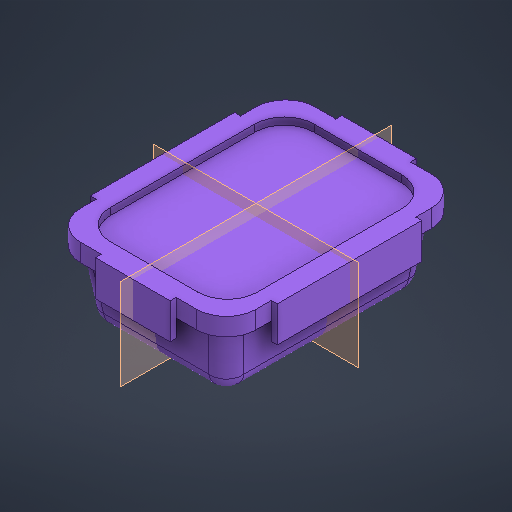
# Autodesk Inventor part: TUPPERWARE
Saved by Autodesk Inventor 2026.1 (Build 301233020, 233B)
## iProperties
Created: 2026-06-04
Part Number: TUPPERWARE
Material: Plastique ABS
Document SubType Name: Modeling
Designer: matpo
Density: 1.06 g/cm^3
Appearance: Violet
Author: matpo
Autodesk Inventor part; units mm, degrees
ref_plane "YZ Plane" through (0, 0, 0) normal (1, 0, 0) x (0, 1, 0)
ref_plane "XZ Plane" through (0, 0, 0) normal (0, 1, 0) x (-1, 0, 0)
sketch "Esquisse1" plane through (0, 0, 0) normal (0, 1, 0) x (-1, 0, 0)
  line L0 (-57.5, 82.5) -> (57.5, 82.5)
  line L1 (57.5, 82.5) -> (57.5, -82.5)
  line L2 (57.5, -82.5) -> (-57.5, -82.5)
  line L3 (-57.5, -82.5) -> (-57.5, 82.5)
  line L4 (-57.5, 82.5) -> (57.5, -82.5) construction
  line L5 (57.5, 82.5) -> (-57.5, -82.5) construction
  line L6 (-65, 90) -> (65, 90)
  line L7 (65, 90) -> (65, -90)
  line L8 (65, -90) -> (-65, -90)
  line L9 (-65, -90) -> (-65, 90)
  line L10 (-65, 90) -> (65, -90) construction
  line L11 (65, 90) -> (-65, -90) construction
  line L12 (-74, 99) -> (74, 99)
  line L13 (74, 99) -> (74, -99)
  line L14 (74, -99) -> (-74, -99)
  line L15 (-74, -99) -> (-74, 99)
  line L16 (-74, 99) -> (74, -99) construction
  line L17 (74, 99) -> (-74, -99) construction
  point P0 (0, 0)
  dimension "d0" = 115
  dimension "d1" = 165
  dimension "d2" = 130
  dimension "d3" = 180
  dimension "d9" = 148
  dimension "d10" = 198
  constraints: 36 end point, 6 midpoint, 6 parallel, 3 horizontal, 3 perpendicular
  measures "d0" distance of L1.end L2.end
  measures "d1" distance of L0.end L1.end
  measures "d2" distance of L7.end L8.end
  measures "d3" distance of L6.end L7.end
  measures "d9" distance of L13.end L14.end
  measures "d10" distance of L12.end L13.end
extrude "Extrusion1" add sketch "Esquisse1" along normal blind 60 contours L0 L1 L2 L3 | L6 L7 L8 L9 | L12 L13 L14 L15
ref_plane "Plan de construction1" through (0, 55, 0) normal (0, 1, 0) x (1, 0, 0)
sketch "Esquisse3" plane through (0, 55, 0) normal (0, 1, 0) x (1, 0, 0)
  line L0 (-65, -90) -> (-65, 90) projected
  line L1 (65, -90) -> (-65, -90) projected
  line L2 (-65, 90) -> (65, 90) projected
  line L3 (65, 90) -> (65, -90) projected
  line L4 (74, 99) -> (-74, 99) projected
  line L5 (74, -99) -> (74, 99) projected
  line L6 (-74, -99) -> (74, -99) projected
  line L7 (-74, 99) -> (-74, -99) projected
extrude "Extrusion2" cut sketch "Esquisse3" against normal through all
sketch "Esquisse4" plane through (-65, 55, 90) normal (0, 0, 1) x (1, 0, 0)
  line L0 (130, -55) -> (0, -55) projected
  line L1 (130, 0) -> (130, -55) projected
  line L2 (130, 0) -> (0, 0) projected
  line L3 (0, 0) -> (0, -55) projected
  line L4 (7.5, -55) -> (0, 0)
  line L5 (122.5, -55) -> (130, 0)
  point P0 (65, -55)
  constraints: 4 end point
extrude "Extrusion3" cut sketch "Esquisse4" against normal through all contours L0 L5 L1 | L0 L3 L4
sketch "Esquisse5" plane through (0, 0, 0) normal (1, 0, 0) x (0, 1, 0)
  line L0 (0, -90) -> (55, -90) projected
  line L1 (0, 90) -> (0, -90) projected
  line L2 (55, 90) -> (0, 90) projected
  line L3 (55, 90) -> (55, -90) projected
  line L4 (0, -82.5) -> (55, -90)
  line L5 (0, 82.5) -> (55, 90)
  point P0 (0, 0)
  constraints: 4 end point
extrude "Extrusion4" cut sketch "Esquisse5" along normal through all both and the other way through all contours L1 L4 L0 | L5 L1 L2
sketch "Esquisse6" plane through (0, 60, 0) normal (0, 1, 0) x (1, 0, 0)
  line L0 (74, 99) -> (-74, 99) projected
  line L1 (-74, 99) -> (-74, -99) projected
  line L2 (-74, -99) -> (74, -99) projected
  line L3 (74, -99) -> (74, 99) projected
  line L4 (69, 61) -> (79, 61)
  line L5 (79, 61) -> (79, -61)
  line L6 (79, -61) -> (69, -61)
  line L7 (69, -61) -> (69, 61)
  line L8 (69, 61) -> (79, -61) construction
  line L9 (79, 61) -> (69, -61) construction
  line L10 (0, 99) -> (0, -99) construction
  line L11 (-74, 0) -> (74, 0) construction
  line L12 (-31.5, -94) -> (31.5, -94)
  line L13 (31.5, -94) -> (31.5, -104)
  line L14 (31.5, -104) -> (-31.5, -104)
  line L15 (-31.5, -104) -> (-31.5, -94)
  line L16 (-31.5, -94) -> (31.5, -104) construction
  line L17 (31.5, -94) -> (-31.5, -104) construction
  line L18 (-69, 61) -> (-79, 61)
  line L19 (-79, 61) -> (-79, -61)
  line L20 (-79, -61) -> (-69, -61)
  line L21 (-69, -61) -> (-69, 61)
  line L22 (-31.5, 94) -> (31.5, 94)
  line L23 (31.5, 94) -> (31.5, 104)
  line L24 (31.5, 104) -> (-31.5, 104)
  line L25 (-31.5, 104) -> (-31.5, 94)
  point P0 (0, 0)
  point P1 (-74, -61)
  point P2 (-74, 61)
  point P3 (31.5, -99)
  point P4 (-31.5, -99)
  point P5 (74, 61)
  point P6 (74, -61)
  point P7 (-31.5, 99)
  point P8 (31.5, 99)
  dimension "d19" = 10
  dimension "d20" = 122
  dimension "d21" = 63
  dimension "d22" = 10
  constraints: 44 end point, 8 midpoint, 8 symmetric about line, 4 parallel, 3 perpendicular, 2 horizontal
  measures "d19" distance of L5.end L6.end
  measures "d20" distance of L4.end L5.end
  measures "d21" distance of L13.end L14.end
  measures "d22" distance of L12.end L13.end
extrude "Extrusion5" add sketch "Esquisse6" along normal blind 10
fillet "Congé1" radius 15 8 edges at (-61.25, 27.5, -86.25) (-57.5, 0, 0) (0, 0, -82.5) (61.25, 27.5, -86.25) (-61.25, 27.5, 86.25) (61.25, 27.5, 86.25) (0, 0, 82.5) (57.5, 0, 0)
fillet "Congé2" radius 25 4 edges at (74, 62.5, -99) (74, 62.5, 99) (-74, 62.5, 99) (-74, 62.5, -99)
sketch "Esquisse7" plane through (0, 60, 0) normal (0, -1, 0) x (1, 0, 0)
  line L0 (-74, -61) -> (-74, 61) projected
  line L1 (-79, 61) -> (-74, 61) projected
  line L2 (-79, -61) -> (-79, 61) projected
  line L3 (-74, -61) -> (-79, -61) projected
  line L4 (31.5, -99) -> (-31.5, -99) projected
  line L5 (-31.5, -104) -> (-31.5, -99) projected
  line L6 (31.5, -104) -> (-31.5, -104) projected
  line L7 (31.5, -99) -> (31.5, -104) projected
  line L8 (74, 61) -> (74, -61) projected
  line L9 (79, -61) -> (74, -61) projected
  line L10 (79, 61) -> (79, -61) projected
  line L11 (74, 61) -> (79, 61) projected
  line L12 (-31.5, 99) -> (31.5, 99) projected
  line L13 (31.5, 104) -> (31.5, 99) projected
  line L14 (-31.5, 104) -> (31.5, 104) projected
  line L15 (-31.5, 99) -> (-31.5, 104) projected
  point P0 (0, 0)
extrude "Extrusion6" add sketch "Esquisse7" along normal blind 20
sketch "Esquisse8" plane through (0, 70, 0) normal (0, 1, 0) x (1, 0, 0)
  line L0 (-37, 86) -> (37, 86)
  line L1 (62, 61) -> (62, -61)
  line L2 (37, -86) -> (-37, -86)
  line L3 (-62, -61) -> (-62, 61)
  line L4 (-62, 86) -> (62, -86) construction
  line L5 (62, 86) -> (-62, -86) construction
  arc A0 (37, -86) -> (62, -61) centre (37, -61) ccw
  arc A1 (-62, -61) -> (-37, -86) centre (-37, -61) ccw
  arc A2 (-37, 86) -> (-62, 61) centre (-37, 61) ccw
  arc A3 (62, 61) -> (37, 86) centre (37, 61) ccw
  point P0 (0, 0)
  dimension "d27" = 124
  dimension "d28" = 172
  dimension "d29" = 25
  constraints: 12 end point, 8 point on circle, 8 point on line, 8 tangent, 4 centre point, 3 equal radius, 2 midpoint, 2 parallel, 1 horizontal, 1 perpendicular
  measures "d27" distance of L4.end L5.end
  measures "d28" distance of L5.start L4.end
  measures "d29" radius of A0
extrude "Extrusion7" cut sketch "Esquisse8" against normal blind 6
ref_plane "Plan de construction3" through (0, 70, 61) normal (1, 0, 0) x (0, 0, -1)
sketch "Esquisse11" plane through (0, 70, 61) normal (1, 0, 0) x (0, 0, -1)
  arc A0 (-23.2691, -57.0267) -> (-8.4066, -70) centre (-8.4066, -55) ccw projected
  line L0 (-23.2691, -57.0267) -> (-29, -15) projected
  arc A1 (130.4066, -70) -> (145.2691, -57.0267) centre (130.4066, -55) ccw projected
  line L1 (151, -15) -> (145.2691, -57.0267) projected
  line L2 (160, -15) -> (135, -15) projected
  line L3 (-13, -15) -> (-38, -15) projected
  line L4 (130.4066, -70) -> (-8.4066, -70) projected
  line L5 (-28.1679, -10) -> (-21.7828, -56.824)
  arc A2 (-21.7828, -56.824) -> (-8.4066, -68.5) centre (-8.4066, -55) ccw
  line L6 (-8.4066, -68.5) -> (130.4066, -68.5)
  arc A3 (130.4066, -68.5) -> (143.7828, -56.824) centre (130.4066, -55) ccw
  line L7 (143.7828, -56.824) -> (150.1679, -10)
  line L8 (-28.1679, -10) -> (150.1679, -10)
  line L9 (0, -6) -> (122, -6) projected
  point P0 (61, -70)
  dimension "d40" = 1.5
  dimension "d41" = 5
  dimension "d42" = 4
  constraints: 8 end point, 4 point on circle, 2 centre point, 1 horizontal, 4 other
  measures "d40" distance between parallel lines of L4 L6
  measures "d41" distance between parallel lines of L8 L3
  measures "d42" distance between parallel lines of L9 L8
extrude "Extrusion8" cut sketch "Esquisse11" along normal mid plane 90 contours L5 L8 L7 A3 L6 A2
ref_plane "Plan de construction4" through (-31.5, 70, 0) normal (0, 0, 1) x (1, 0, 0)
sketch "Esquisse12" plane through (-31.5, 70, 0) normal (0, 0, 1) x (1, 0, 0)
  line L0 (-27.7691, -57.0267) -> (-33.5, -15) projected
  line L1 (-13.5, -10) -> (76.5, -10) projected
  arc A0 (-27.7691, -57.0267) -> (-12.9066, -70) centre (-12.9066, -55) ccw projected
  line L2 (75.9066, -70) -> (-12.9066, -70) projected
  arc A1 (75.9066, -70) -> (90.7691, -57.0267) centre (75.9066, -55) ccw projected
  line L3 (96.5, -15) -> (90.7691, -57.0267) projected
  line L4 (-13.5, -68.5) -> (76.5, -68.5) projected
  line L5 (95.6679, -10) -> (89.2828, -56.824)
  arc A2 (75.9066, -68.5) -> (89.2828, -56.824) centre (75.9066, -55) ccw
  line L6 (75.9066, -68.5) -> (-12.9066, -68.5)
  arc A3 (-26.2828, -56.824) -> (-12.9066, -68.5) centre (-12.9066, -55) ccw
  line L7 (-26.2828, -56.824) -> (-32.6679, -10)
  line L8 (-32.6679, -10) -> (95.6679, -10)
  point P0 (31.5, -70)
  point P1 (31.5, -10)
  point P2 (-12.9066, -68.5)
  point P3 (75.9066, -68.5)
  dimension "d45" = 1.5
  constraints: 8 end point, 4 point on circle, 2 centre point, 2 midpoint, 1 horizontal, 4 other
  measures "d45" distance between parallel lines of L2 L6
extrude "Extrusion9" cut sketch "Esquisse12" along normal mid plane 140
sketch "Esquisse15" plane through (-31.5, 70, 70) normal (0, 0, -1) x (-1, 0, 0)
  line L0 (13.5, -68.487) -> (13.5, -10) projected
  arc A0 (13.5, -68.487) -> (26.2828, -56.824) centre (12.9066, -55) ccw projected
  line L1 (32.6679, -10) -> (26.2828, -56.824) projected
  line L2 (13.5, -10) -> (32.6679, -10) projected
  point P0 (-31.5, -70)
revolve "Révolution1" cut sketch "Esquisse15" angle 360 about axis through (-45, 1.513, 70) along (0, 1, 0)
sketch "Esquisse16" plane through (-31.5, 70, 70) normal (0, 0, -1) x (-1, 0, 0)
  line L0 (-76.5, -10) -> (-76.5, -68.487) projected
  line L1 (-95.6679, -10) -> (-76.5, -10) projected
  line L2 (-89.2828, -56.824) -> (-95.6679, -10) projected
  arc A0 (-89.2828, -56.824) -> (-76.5, -68.487) centre (-75.9066, -55) ccw projected
  point P0 (-31.5, -70)
revolve "Révolution2" cut sketch "Esquisse16" angle 360 about axis through (45, 60, 70) along (0, -1, 0)
sketch "Esquisse17" plane through (-31.5, 70, -70) normal (0, 0, 1) x (1, 0, 0)
  line L0 (-13.5, -10) -> (-13.5, -68.487) projected
  line L1 (-32.6679, -10) -> (-13.5, -10) projected
  line L2 (-26.2828, -56.824) -> (-32.6679, -10) projected
  arc A0 (-26.2828, -56.824) -> (-13.5, -68.487) centre (-12.9066, -55) ccw projected
  point P0 (31.5, -70)
revolve "Révolution3" cut sketch "Esquisse17" angle 360 about axis through (-45, 60, -70) along (0, -1, 0)
sketch "Esquisse18" plane through (-31.5, 70, -70) normal (0, 0, 1) x (1, 0, 0)
  line L0 (76.5, -68.487) -> (76.5, -10) projected
  arc A0 (76.5, -68.487) -> (89.2828, -56.824) centre (75.9066, -55) ccw projected
  line L1 (95.6679, -10) -> (89.2828, -56.824) projected
  line L2 (76.5, -10) -> (95.6679, -10) projected
  point P0 (31.5, -70)
revolve "Révolution4" cut sketch "Esquisse18" angle 360 about axis through (45, 1.513, -70) along (0, 1, 0)
